Autodesk Fusion 360 part; units mm, degrees
(part 3 of 4)
sketch "ProMicro" plane through (0, 0, 0) normal (0, 0, -1) x (1, 0, 0) in component "Plate_Left"
  line L0 (111.75, 39.3) -> (111.75, 25.3)
  line L1 (101.75, 25.3) -> (97.75, 25.3)
  line L2 (97.75, 25.3) -> (97.75, 39.3)
  line L3 (97.75, 39.3) -> (101.75, 39.3)
  line L4 (92.7, 55.69) -> (92.7, 41.69)
  line L5 (92.7, 41.69) -> (88.7, 41.69)
  line L6 (78.7, 41.69) -> (78.7, 55.69)
  line L7 (88.7, 55.69) -> (92.7, 55.69)
  line L8 (59.65, 78.7) -> (59.65, 92.7)
  line L9 (59.65, 92.7) -> (63.65, 92.7)
  line L10 (73.65, 92.7) -> (73.65, 78.7)
  line L11 (63.65, 78.7) -> (59.65, 78.7)
  line L12 (59.65, 16.5) -> (63.65, 16.5)
  line L13 (73.65, 16.5) -> (73.65, 2.5)
  line L14 (63.65, 2.5) -> (59.65, 2.5)
  line L15 (59.65, 2.5) -> (59.65, 16.5)
  line L16 (40.6, 79.79) -> (40.6, 93.79)
  line L17 (40.6, 93.79) -> (44.6, 93.79)
  line L18 (54.6, 93.79) -> (54.6, 79.79)
  line L19 (44.6, 79.79) -> (40.6, 79.79)
  line L20 (31.55, 21.21) -> (35.55, 21.21)
  line L21 (35.55, 21.21) -> (35.55, 7.21)
  line L22 (35.55, 7.21) -> (31.55, 7.21)
  line L23 (21.55, 7.21) -> (21.55, 21.21)
  line L24 (12.5, 79.5) -> (16.5, 79.5)
  line L25 (16.5, 79.5) -> (16.5, 65.5)
  line L26 (16.5, 65.5) -> (12.5, 65.5)
  line L27 (2.5, 65.5) -> (2.5, 79.5)
  line L28 (2.5, 98.55) -> (6.5, 98.55)
  line L29 (16.5, 98.55) -> (16.5, 84.55)
  line L30 (6.5, 84.55) -> (2.5, 84.55)
  line L31 (2.5, 84.55) -> (2.5, 98.55)
  line L32 (2.5, 60.45) -> (6.5, 60.45)
  line L33 (16.5, 60.45) -> (16.5, 46.45)
  line L34 (6.5, 46.45) -> (2.5, 46.45)
  line L35 (2.5, 46.45) -> (2.5, 60.45)
  line L36 (35.55, 40.26) -> (35.55, 26.26)
  line L37 (25.55, 26.26) -> (21.55, 26.26)
  line L38 (21.55, 26.26) -> (21.55, 40.26)
  line L39 (21.55, 40.26) -> (25.55, 40.26)
  line L40 (54.6, 55.69) -> (54.6, 41.69)
  line L41 (54.6, 41.69) -> (50.6, 41.69)
  line L42 (40.6, 41.69) -> (40.6, 55.69)
  line L43 (50.6, 55.69) -> (54.6, 55.69)
  line L44 (73.65, 35.55) -> (73.65, 21.55)
  line L45 (63.65, 21.55) -> (59.65, 21.55)
  line L46 (59.65, 21.55) -> (59.65, 35.55)
  line L47 (59.65, 35.55) -> (63.65, 35.55)
  line L48 (90.1617, 83.0445) -> (84.4545, 95.8284)
  line L49 (93.5858, 99.9049) -> (97.2384, 101.5355)
  line L50 (97.2384, 101.5355) -> (102.9456, 88.7516)
  line L51 (102.9456, 88.7516) -> (99.293, 87.121)
  line L52 (92.7, 36.64) -> (92.7, 22.64)
  line L53 (82.7, 22.64) -> (78.7, 22.64)
  line L54 (78.7, 22.64) -> (78.7, 36.64)
  line L55 (78.7, 36.64) -> (82.7, 36.64)
  line L56 (111.75, 58.35) -> (111.75, 44.35)
  line L57 (111.75, 44.35) -> (107.75, 44.35)
  line L58 (97.75, 44.35) -> (97.75, 58.35)
  line L59 (107.75, 58.35) -> (111.75, 58.35)
  line L60 (107.75, 20.25) -> (111.75, 20.25)
  line L61 (111.75, 20.25) -> (111.75, 6.25)
  line L62 (111.75, 6.25) -> (107.75, 6.25)
  line L63 (97.75, 6.25) -> (97.75, 20.25)
  line L64 (78.7, 60.74) -> (78.7, 74.74)
  line L65 (88.7, 74.74) -> (92.7, 74.74)
  line L66 (92.7, 74.74) -> (92.7, 60.74)
  line L67 (92.7, 60.74) -> (88.7, 60.74)
  line L68 (59.65, 59.65) -> (59.65, 73.65)
  line L69 (69.65, 73.65) -> (73.65, 73.65)
  line L70 (73.65, 73.65) -> (73.65, 59.65)
  line L71 (73.65, 59.65) -> (69.65, 59.65)
  line L72 (40.6, 17.59) -> (44.6, 17.59)
  line L73 (54.6, 17.59) -> (54.6, 3.59)
  line L74 (44.6, 3.59) -> (40.6, 3.59)
  line L75 (40.6, 3.59) -> (40.6, 17.59)
  line L76 (40.6, 60.74) -> (40.6, 74.74)
  line L77 (50.6, 74.74) -> (54.6, 74.74)
  line L78 (54.6, 74.74) -> (54.6, 60.74)
  line L79 (54.6, 60.74) -> (50.6, 60.74)
  line L80 (16.5, 22.35) -> (16.5, 8.35)
  line L81 (16.5, 8.35) -> (12.5, 8.35)
  line L82 (2.5, 8.35) -> (2.5, 22.35)
  line L83 (12.5, 22.35) -> (16.5, 22.35)
  line L84 (21.55, 64.36) -> (21.55, 78.36)
  line L85 (31.55, 78.36) -> (35.55, 78.36)
  line L86 (35.55, 78.36) -> (35.55, 64.36)
  line L87 (35.55, 64.36) -> (31.55, 64.36)
  line L88 (21.55, 83.41) -> (21.55, 97.41)
  line L89 (21.55, 97.41) -> (25.55, 97.41)
  line L90 (35.55, 97.41) -> (35.55, 83.41)
  line L91 (25.55, 83.41) -> (21.55, 83.41)
  line L92 (2.5, 27.4) -> (2.5, 41.4)
  line L93 (12.5, 41.4) -> (16.5, 41.4)
  line L94 (16.5, 41.4) -> (16.5, 27.4)
  line L95 (16.5, 27.4) -> (12.5, 27.4)
  line L96 (35.55, 59.31) -> (35.55, 45.31)
  line L97 (35.55, 45.31) -> (31.55, 45.31)
  line L98 (21.55, 45.31) -> (21.55, 59.31)
  line L99 (31.55, 59.31) -> (35.55, 59.31)
  line L100 (54.6, 36.64) -> (54.6, 22.64)
  line L101 (44.6, 22.64) -> (40.6, 22.64)
  line L102 (40.6, 22.64) -> (40.6, 36.64)
  line L103 (40.6, 36.64) -> (44.6, 36.64)
  line L104 (73.65, 54.6) -> (73.65, 40.6)
  line L105 (63.65, 40.6) -> (59.65, 40.6)
  line L106 (59.65, 40.6) -> (59.65, 54.6)
  line L107 (59.65, 54.6) -> (63.65, 54.6)
  line L108 (112.7117, 92.7045) -> (107.0045, 105.4884)
  line L109 (116.1358, 109.5649) -> (119.7884, 111.1955)
  line L110 (119.7884, 111.1955) -> (125.4956, 98.4116)
  line L111 (125.4956, 98.4116) -> (121.843, 96.781)
  line L112 (88.7, 17.59) -> (92.7, 17.59)
  line L113 (92.7, 17.59) -> (92.7, 3.59)
  line L114 (92.7, 3.59) -> (88.7, 3.59)
  line L115 (78.7, 3.59) -> (78.7, 17.59)
  line L116 (97.75, 63.4) -> (97.75, 77.4)
  line L117 (107.75, 77.4) -> (111.75, 77.4)
  line L118 (111.75, 77.4) -> (111.75, 63.4)
  line L119 (111.75, 63.4) -> (107.75, 63.4)
  line L120 (119.3123, 118.9999) -> (83.6581, 103.172)
  arc A0 (82.8467, 103) -> (83.6581, 103.172) centre (82.8467, 105) ccw
  line L121 (82.8467, 103) -> (0, 103)
  arc A1 (0, 103) -> (-6, 97) centre (0, 97) ccw
  line L122 (-6, 97) -> (-6, 6.0028)
  arc A2 (-6, 6.0028) -> (0, 0.0028) centre (0, 6.0028) ccw
  line L123 (0, 0.0028) -> (135.25, 0.0028)
  arc A3 (135.25, 0.0028) -> (141.25, 6.0028) centre (135.25, 6.0028) ccw
  line L124 (141.25, 6.0028) -> (141.25, 113.172)
  arc A4 (141.25, 113.172) -> (135.25, 119.172) centre (135.25, 113.172) ccw
  line L125 (135.25, 119.172) -> (120.1238, 119.172)
  arc A5 (120.1238, 119.172) -> (119.3123, 118.9999) centre (120.1238, 117.172) ccw
  line L126 (114.2279, 1.5198) -> (114.2279, 35.3198)
  line L127 (114.2279, 35.3198) -> (132.7279, 35.3198)
  line L128 (132.7279, 35.3198) -> (132.7279, 1.5198)
  line L129 (132.7279, 1.5198) -> (114.2279, 1.5198)
  line L130 (118.9079, 0.0181) -> (118.9079, 1.5198)
  line L131 (127.8479, 1.5198) -> (127.8479, 0.0181)
  line L132 (118.9079, 0.0181) -> (127.8479, 0.0181)
  line L133 (126.4779, 35.3198) -> (120.4779, 35.3198)
  line L134 (126.4779, 35.3198) -> (126.4779, 34.3198)
  line L135 (126.4779, 34.3198) -> (120.4779, 34.3198)
  line L136 (120.4779, 34.3198) -> (120.4779, 35.3198)
  line L137 (126.4779, 35.3198) -> (126.4779, 36.3198)
  line L138 (126.4779, 36.3198) -> (120.4779, 36.3198)
  line L139 (120.4779, 36.3198) -> (120.4779, 35.3198)
  line L140 (101.75, 58.35) -> (101.75, 59.85)
  line L141 (101.75, 59.85) -> (107.75, 59.85)
  line L142 (107.75, 59.85) -> (107.75, 58.35)
  line L143 (107.75, 44.35) -> (107.75, 42.85)
  line L144 (107.75, 42.85) -> (101.75, 42.85)
  line L145 (101.75, 42.85) -> (101.75, 44.35)
  line L146 (101.75, 44.35) -> (97.75, 44.35)
  line L147 (97.75, 58.35) -> (101.75, 58.35)
  line L148 (88.7, 19.09) -> (88.7, 17.59)
  line L149 (88.7, 3.59) -> (88.7, 2.09)
  line L150 (88.7, 2.09) -> (82.7, 2.09)
  line L151 (82.7, 2.09) -> (82.7, 3.59)
  line L152 (82.7, 3.59) -> (78.7, 3.59)
  line L153 (78.7, 17.59) -> (82.7, 17.59)
  line L154 (82.7, 17.59) -> (82.7, 19.09)
  line L155 (82.7, 19.09) -> (88.7, 19.09)
  line L156 (88.7, 57.19) -> (88.7, 55.69)
  line L157 (88.7, 41.69) -> (88.7, 40.19)
  line L158 (88.7, 40.19) -> (82.7, 40.19)
  line L159 (82.7, 40.19) -> (82.7, 41.69)
  line L160 (82.7, 41.69) -> (78.7, 41.69)
  line L161 (78.7, 55.69) -> (82.7, 55.69)
  line L162 (82.7, 55.69) -> (82.7, 57.19)
  line L163 (82.7, 57.19) -> (88.7, 57.19)
  line L164 (101.75, 23.8) -> (101.75, 25.3)
  line L165 (101.75, 39.3) -> (101.75, 40.8)
  line L166 (101.75, 40.8) -> (107.75, 40.8)
  line L167 (107.75, 40.8) -> (107.75, 39.3)
  line L168 (107.75, 39.3) -> (111.75, 39.3)
  line L169 (111.75, 25.3) -> (107.75, 25.3)
  line L170 (107.75, 25.3) -> (107.75, 23.8)
  line L171 (107.75, 23.8) -> (101.75, 23.8)
  line L172 (107.75, 21.75) -> (107.75, 20.25)
  line L173 (107.75, 6.25) -> (107.75, 4.75)
  line L174 (107.75, 4.75) -> (101.75, 4.75)
  line L175 (101.75, 4.75) -> (101.75, 6.25)
  line L176 (101.75, 6.25) -> (97.75, 6.25)
  line L177 (97.75, 20.25) -> (101.75, 20.25)
  line L178 (101.75, 20.25) -> (101.75, 21.75)
  line L179 (101.75, 21.75) -> (107.75, 21.75)
  line L180 (82.7, 21.14) -> (82.7, 22.64)
  line L181 (82.7, 36.64) -> (82.7, 38.14)
  line L182 (82.7, 38.14) -> (88.7, 38.14)
  line L183 (88.7, 38.14) -> (88.7, 36.64)
  line L184 (88.7, 36.64) -> (92.7, 36.64)
  line L185 (92.7, 22.64) -> (88.7, 22.64)
  line L186 (88.7, 22.64) -> (88.7, 21.14)
  line L187 (88.7, 21.14) -> (82.7, 21.14)
  line L188 (88.7, 76.24) -> (88.7, 74.74)
  line L189 (88.7, 60.74) -> (88.7, 59.24)
  line L190 (88.7, 59.24) -> (82.7, 59.24)
  line L191 (82.7, 59.24) -> (82.7, 60.74)
  line L192 (82.7, 60.74) -> (78.7, 60.74)
  line L193 (78.7, 74.74) -> (82.7, 74.74)
  line L194 (82.7, 74.74) -> (82.7, 76.24)
  line L195 (82.7, 76.24) -> (88.7, 76.24)
  line L196 (63.65, 77.2) -> (63.65, 78.7)
  line L197 (63.65, 92.7) -> (63.65, 94.2)
  line L198 (63.65, 94.2) -> (69.65, 94.2)
  line L199 (69.65, 94.2) -> (69.65, 92.7)
  line L200 (69.65, 92.7) -> (73.65, 92.7)
  line L201 (73.65, 78.7) -> (69.65, 78.7)
  line L202 (69.65, 78.7) -> (69.65, 77.2)
  line L203 (69.65, 77.2) -> (63.65, 77.2)
  line L204 (50.6, 76.24) -> (50.6, 74.74)
  line L205 (50.6, 60.74) -> (50.6, 59.24)
  line L206 (50.6, 59.24) -> (44.6, 59.24)
  line L207 (44.6, 59.24) -> (44.6, 60.74)
  line L208 (44.6, 60.74) -> (40.6, 60.74)
  line L209 (40.6, 74.74) -> (44.6, 74.74)
  line L210 (44.6, 74.74) -> (44.6, 76.24)
  line L211 (44.6, 76.24) -> (50.6, 76.24)
  line L212 (25.55, 81.91) -> (25.55, 83.41)
  line L213 (25.55, 97.41) -> (25.55, 98.91)
  line L214 (25.55, 98.91) -> (31.55, 98.91)
  line L215 (31.55, 98.91) -> (31.55, 97.41)
  line L216 (31.55, 97.41) -> (35.55, 97.41)
  line L217 (35.55, 83.41) -> (31.55, 83.41)
  line L218 (31.55, 83.41) -> (31.55, 81.91)
  line L219 (31.55, 81.91) -> (25.55, 81.91)
  line L220 (63.65, 39.1) -> (63.65, 40.6)
  line L221 (63.65, 54.6) -> (63.65, 56.1)
  line L222 (63.65, 56.1) -> (69.65, 56.1)
  line L223 (69.65, 56.1) -> (69.65, 54.6)
  line L224 (69.65, 54.6) -> (73.65, 54.6)
  line L225 (73.65, 40.6) -> (69.65, 40.6)
  line L226 (69.65, 40.6) -> (69.65, 39.1)
  line L227 (69.65, 39.1) -> (63.65, 39.1)
  line L228 (25.55, 24.76) -> (25.55, 26.26)
  line L229 (25.55, 40.26) -> (25.55, 41.76)
  line L230 (25.55, 41.76) -> (31.55, 41.76)
  line L231 (31.55, 41.76) -> (31.55, 40.26)
  line L232 (31.55, 40.26) -> (35.55, 40.26)
  line L233 (35.55, 26.26) -> (31.55, 26.26)
  line L234 (31.55, 26.26) -> (31.55, 24.76)
  line L235 (31.55, 24.76) -> (25.55, 24.76)
  line L236 (12.5, 42.9) -> (12.5, 41.4)
  line L237 (12.5, 27.4) -> (12.5, 25.9)
  line L238 (12.5, 25.9) -> (6.5, 25.9)
  line L239 (6.5, 25.9) -> (6.5, 27.4)
  line L240 (6.5, 27.4) -> (2.5, 27.4)
  line L241 (2.5, 41.4) -> (6.5, 41.4)
  line L242 (6.5, 41.4) -> (6.5, 42.9)
  line L243 (6.5, 42.9) -> (12.5, 42.9)
  line L244 (12.5, 23.85) -> (12.5, 22.35)
  line L245 (12.5, 8.35) -> (12.5, 6.85)
  line L246 (12.5, 6.85) -> (6.5, 6.85)
  line L247 (6.5, 6.85) -> (6.5, 8.35)
  line L248 (6.5, 8.35) -> (2.5, 8.35)
  line L249 (2.5, 22.35) -> (6.5, 22.35)
  line L250 (6.5, 22.35) -> (6.5, 23.85)
  line L251 (6.5, 23.85) -> (12.5, 23.85)
  line L252 (44.6, 21.14) -> (44.6, 22.64)
  line L253 (44.6, 36.64) -> (44.6, 38.14)
  line L254 (44.6, 38.14) -> (50.6, 38.14)
  line L255 (50.6, 38.14) -> (50.6, 36.64)
  line L256 (50.6, 36.64) -> (54.6, 36.64)
  line L257 (54.6, 22.64) -> (50.6, 22.64)
  line L258 (50.6, 22.64) -> (50.6, 21.14)
  line L259 (50.6, 21.14) -> (44.6, 21.14)
  line L260 (63.65, 20.05) -> (63.65, 21.55)
  line L261 (63.65, 35.55) -> (63.65, 37.05)
  line L262 (63.65, 37.05) -> (69.65, 37.05)
  line L263 (69.65, 37.05) -> (69.65, 35.55)
  line L264 (69.65, 35.55) -> (73.65, 35.55)
  line L265 (73.65, 21.55) -> (69.65, 21.55)
  line L266 (69.65, 21.55) -> (69.65, 20.05)
  line L267 (69.65, 20.05) -> (63.65, 20.05)
  line L268 (31.55, 60.81) -> (31.55, 59.31)
  line L269 (31.55, 45.31) -> (31.55, 43.81)
  line L270 (31.55, 43.81) -> (25.55, 43.81)
  line L271 (25.55, 43.81) -> (25.55, 45.31)
  line L272 (25.55, 45.31) -> (21.55, 45.31)
  line L273 (21.55, 59.31) -> (25.55, 59.31)
  line L274 (25.55, 59.31) -> (25.55, 60.81)
  line L275 (25.55, 60.81) -> (31.55, 60.81)
  line L276 (6.5, 83.05) -> (6.5, 84.55)
  line L277 (6.5, 98.55) -> (6.5, 100.05)
  line L278 (6.5, 100.05) -> (12.5, 100.05)
  line L279 (12.5, 100.05) -> (12.5, 98.55)
  line L280 (12.5, 98.55) -> (16.5, 98.55)
  line L281 (16.5, 84.55) -> (12.5, 84.55)
  line L282 (12.5, 84.55) -> (12.5, 83.05)
  line L283 (12.5, 83.05) -> (6.5, 83.05)
  line L284 (31.55, 79.86) -> (31.55, 78.36)
  line L285 (31.55, 64.36) -> (31.55, 62.86)
  line L286 (31.55, 62.86) -> (25.55, 62.86)
  line L287 (25.55, 62.86) -> (25.55, 64.36)
  line L288 (25.55, 64.36) -> (21.55, 64.36)
  line L289 (21.55, 78.36) -> (25.55, 78.36)
  line L290 (25.55, 78.36) -> (25.55, 79.86)
  line L291 (25.55, 79.86) -> (31.55, 79.86)
  line L292 (107.75, 78.9) -> (107.75, 77.4)
  line L293 (107.75, 63.4) -> (107.75, 61.9)
  line L294 (107.75, 61.9) -> (101.75, 61.9)
  line L295 (101.75, 61.9) -> (101.75, 63.4)
  line L296 (101.75, 63.4) -> (97.75, 63.4)
  line L297 (97.75, 77.4) -> (101.75, 77.4)
  line L298 (101.75, 77.4) -> (101.75, 78.9)
  line L299 (101.75, 78.9) -> (107.75, 78.9)
  line L300 (6.5, 79.5) -> (6.5, 81)
  line L301 (6.5, 81) -> (12.5, 81)
  line L302 (12.5, 81) -> (12.5, 79.5)
  line L303 (12.5, 65.5) -> (12.5, 64)
  line L304 (12.5, 64) -> (6.5, 64)
  line L305 (6.5, 64) -> (6.5, 65.5)
  line L306 (6.5, 65.5) -> (2.5, 65.5)
  line L307 (2.5, 79.5) -> (6.5, 79.5)
  line L308 (44.6, 55.69) -> (44.6, 57.19)
  line L309 (44.6, 57.19) -> (50.6, 57.19)
  line L310 (50.6, 57.19) -> (50.6, 55.69)
  line L311 (50.6, 41.69) -> (50.6, 40.19)
  line L312 (50.6, 40.19) -> (44.6, 40.19)
  line L313 (44.6, 40.19) -> (44.6, 41.69)
  line L314 (44.6, 41.69) -> (40.6, 41.69)
  line L315 (40.6, 55.69) -> (44.6, 55.69)
  line L316 (25.55, 21.21) -> (25.55, 22.71)
  line L317 (25.55, 22.71) -> (31.55, 22.71)
  line L318 (31.55, 22.71) -> (31.55, 21.21)
  line L319 (31.55, 7.21) -> (31.55, 5.71)
  line L320 (31.55, 5.71) -> (25.55, 5.71)
  line L321 (25.55, 5.71) -> (25.55, 7.21)
  line L322 (25.55, 7.21) -> (21.55, 7.21)
  line L323 (21.55, 21.21) -> (25.55, 21.21)
  line L324 (63.65, 1) -> (63.65, 2.5)
  line L325 (63.65, 16.5) -> (63.65, 18)
  line L326 (63.65, 18) -> (69.65, 18)
  line L327 (69.65, 18) -> (69.65, 16.5)
  line L328 (69.65, 16.5) -> (73.65, 16.5)
  line L329 (73.65, 2.5) -> (69.65, 2.5)
  line L330 (69.65, 2.5) -> (69.65, 1)
  line L331 (69.65, 1) -> (63.65, 1)
  line L332 (63.65, 73.65) -> (63.65, 75.15)
  line L333 (63.65, 75.15) -> (69.65, 75.15)
  line L334 (69.65, 75.15) -> (69.65, 73.65)
  line L335 (69.65, 59.65) -> (69.65, 58.15)
  line L336 (69.65, 58.15) -> (63.65, 58.15)
  line L337 (63.65, 58.15) -> (63.65, 59.65)
  line L338 (63.65, 59.65) -> (59.65, 59.65)
  line L339 (59.65, 73.65) -> (63.65, 73.65)
  line L340 (50.6, 79.79) -> (50.6, 78.29)
  line L341 (50.6, 78.29) -> (44.6, 78.29)
  line L342 (44.6, 78.29) -> (44.6, 79.79)
  line L343 (44.6, 93.79) -> (44.6, 95.29)
  line L344 (44.6, 95.29) -> (50.6, 95.29)
  line L345 (50.6, 95.29) -> (50.6, 93.79)
  line L346 (50.6, 93.79) -> (54.6, 93.79)
  line L347 (54.6, 79.79) -> (50.6, 79.79)
  line L348 (12.5, 46.45) -> (12.5, 44.95)
  line L349 (12.5, 44.95) -> (6.5, 44.95)
  line L350 (6.5, 44.95) -> (6.5, 46.45)
  line L351 (6.5, 60.45) -> (6.5, 61.95)
  line L352 (6.5, 61.95) -> (12.5, 61.95)
  line L353 (12.5, 61.95) -> (12.5, 60.45)
  line L354 (12.5, 60.45) -> (16.5, 60.45)
  line L355 (16.5, 46.45) -> (12.5, 46.45)
  line L356 (50.6, 3.59) -> (50.6, 2.09)
  line L357 (50.6, 2.09) -> (44.6, 2.09)
  line L358 (44.6, 2.09) -> (44.6, 3.59)
  line L359 (44.6, 17.59) -> (44.6, 19.09)
  line L360 (44.6, 19.09) -> (50.6, 19.09)
  line L361 (50.6, 19.09) -> (50.6, 17.59)
  line L362 (50.6, 17.59) -> (54.6, 17.59)
  line L363 (54.6, 3.59) -> (50.6, 3.59)
  line L364 (92.9744, 101.2746) -> (93.5858, 99.9049)
  line L365 (99.293, 87.121) -> (99.9045, 85.7513)
  line L366 (99.9045, 85.7513) -> (94.4257, 83.3054)
  line L367 (94.4257, 83.3054) -> (93.8142, 84.6751)
  line L368 (93.8142, 84.6751) -> (90.1617, 83.0445)
  line L369 (84.4545, 95.8284) -> (88.107, 97.459)
  line L370 (88.107, 97.459) -> (87.4955, 98.8287)
  line L371 (87.4955, 98.8287) -> (92.9744, 101.2746)
  line L372 (115.5244, 110.9346) -> (116.1358, 109.5649)
  line L373 (121.843, 96.781) -> (122.4545, 95.4113)
  line L374 (122.4545, 95.4113) -> (116.9757, 92.9654)
  line L375 (116.9757, 92.9654) -> (116.3642, 94.3351)
  line L376 (116.3642, 94.3351) -> (112.7117, 92.7045)
  line L377 (107.0045, 105.4884) -> (110.657, 107.119)
  line L378 (110.657, 107.119) -> (110.0455, 108.4887)
  line L379 (110.0455, 108.4887) -> (115.5244, 110.9346)
  line L380 (117.2279, 35.3198) -> (117.2279, 15.3198)
  line L381 (117.2279, 15.3198) -> (129.7279, 15.3198)
  line L382 (129.7279, 15.3198) -> (129.7279, 35.3198)
  line L383 (129.7279, 15.3198) -> (132.7279, 15.3198) construction
  line L384 (117.2279, 15.3198) -> (114.2279, 15.3198) construction
  line L385 (141.25, 45.3198) -> (126.75, 45.3198)
  line L386 (126.75, 45.3198) -> (126.75, 54.3198)
  line L387 (126.75, 54.3198) -> (141.25, 54.3198)
  line L388 (141.25, 54.3198) -> (141.25, 45.3198)
  point P0 (123.4779, 1.5198)
  point P1 (123.4779, 35.3198)
  dimension "d218" = 33.8
  dimension "d219" = 18.5
  dimension "d220" = 8.94
  dimension "d221" = 1.5017
  dimension "d222" = 4.68
  dimension "d227" = 6
  dimension "d228" = 1
  dimension "d229" = 1
  dimension "d453" = 20
  dimension "d454" = 3
  dimension "d495" = 14.5
  dimension "d496" = 9
  dimension "d497" = 10
  constraint coincident L129 L131.start
  constraint perpendicular L129 L131
  constraint coincident L129 L130.end
  constraint perpendicular L129 L130
  constraint perpendicular L131 L132
  constraint perpendicular L126 L129
  constraint perpendicular L128 L129
  constraint perpendicular L127 L128
  constraint vertical L126
  constraint midpoint L129 P0
  constraint midpoint L127 P1
  constraint parallel L127 L133
  constraint midpoint P1 L133
  constraint perpendicular L133 L134
  constraint perpendicular L134 L135
  constraint perpendicular L127 L136
  constraint perpendicular L127 L137
  constraint perpendicular L136 L138
  constraint perpendicular L133 L139
  constraint coincident L127 L380.start
  constraint perpendicular L127 L380
  constraint perpendicular L380 L381
  constraint coincident L127 L382.end
  constraint perpendicular L127 L382
  constraint coincident L128 L383.end
  constraint perpendicular L128 L383
  constraint coincident L126 L384.end
  constraint perpendicular L126 L384
  constraint equal L383 L384
  constraint horizontal L385
  constraint vertical L386
  constraint horizontal L387
  constraint vertical L388
  constraint coincident L124 L385.start
  measures "d218" distance of L127.end L128.end
  measures "d219" distance of L126.start L128.end
  measures "d220" distance of L130.start L131.end
  measures "d221" distance of L130.start L130.end
  measures "d222" distance of L126.start L130.end
  measures "d227" distance of L133.start L133.end
  measures "d228" distance of L133.start L134.end
  measures "d229" distance of L133.start L137.end
  measures "d453" distance of L380.start L380.end
  measures "d454" distance of L380.end L384.end
  measures "d495" distance of L385.start L385.end
  measures "d496" distance of L385.start L387.end
  measures "d497" distance of L127 L385
extrude "Extrude6" cut sketch "ProMicro" against normal blind 1.6 contours L126 L127 L128 L129 L380 L381 L382 | L127 L134 L135 L136 L380 L381 L382 | L127 L133 L134 L135 L136 bodies 1 in component "Plate_Left"
extrude "Extrude14" cut sketch "ProMicro" against normal blind 0.8 from surface at -1.6 contours L126 L127 L128 L129 L380 L381 L382 bodies 1 in component "Plate_Left"
extrude "Extrude8" add sketch "ProMicro" along normal blind 1 contours L127 L133 L137 L138 L139 | L127 L133 L134 L135 L136 bodies 1 in component "Plate_Left"
fillet "Fillet3" radius 1 1 edges at (123.4779, -34.3198, 0) on bodies 1 in component "Plate_Left"
chamfer "Chamfer1" distance 0.5 angle 45 3 edges at (126.4779, -35.8198, 0) (123.4779, -36.3198, 0) (120.4779, -35.8198, 0) on bodies 1 in component "Plate_Left"
fillet "Fillet4" radius 0.4 1 edges at (123.4779, -34.3198, -1) on bodies 1 in component "Plate_Left"
sketch "USB_C_MCU" plane through (0, -0.0028, 0) normal (0, 1, 0) x (-1, 0, 0) in component "Plate_Left"
  line L0 (-135.25, 5) -> (-135.25, 0)
  line L1 (-135.25, 0) -> (0, 0)
  line L2 (0, 0) -> (0, 5)
  line L3 (-132.7279, 0) -> (-132.7279, 2.4)
  line L4 (-118.9779, -1.45) -> (-118.9779, -0.7)
  line L5 (-120.1779, 0.5) -> (-126.7779, 0.5)
  line L6 (-127.9779, -0.7) -> (-127.9779, -1.45)
  arc A0 (-120.1779, -2.65) -> (-118.9779, -1.45) centre (-120.1779, -1.45) ccw
  arc A1 (-118.9779, -0.7) -> (-120.1779, 0.5) centre (-120.1779, -0.7) ccw
  arc A2 (-127.9779, -1.45) -> (-126.7779, -2.65) centre (-126.7779, -1.45) ccw
  line L7 (-126.7779, -2.65) -> (-120.1779, -2.65)
  arc A3 (-126.7779, 0.5) -> (-127.9779, -0.7) centre (-126.7779, -0.7) ccw
  line L8 (-129.7279, 1.6) -> (-117.2279, 1.6)
  line L9 (-123.4779, 0.5) -> (-123.4779, 1.6) construction
  line L10 (0, 5) -> (-135.25, 5)
  line L11 (-117.2279, 1.6) -> (-129.7279, 1.6)
  dimension "d443" = 1.1
  dimension "d444" = 0.75
  dimension "d445" = 1.2
  dimension "d446" = 6.6
  dimension "d447" = 9
  dimension "d448" = 3.15
  constraint vertical L9
  constraint midpoint L5 L9.start
  constraint equal L5 L7
  constraint horizontal L7
  constraint horizontal L5
  constraint vertical L4
  constraint vertical L6
  constraint equal L4 L6
  constraint equal A1 A2
  constraint equal A0 A3
  constraint equal A0 A2
  measures "d443" distance of L9.start L9.end
  measures "d444" distance of L4.end L4.start
  measures "d445" radius of A2
  measures "d446" distance of A2.end A0.start
  measures "d447" distance of L4 L6
  measures "d448" distance of L5 L7
sketch "Sketch10" plane through (141.25, 0, 0) normal (1, 0, 0) x (0, 1, 0) in component "Plate_Left"
  line L0 (-113.172, 0) -> (-6.0028, 0)
  line L1 (-6.0028, 0) -> (-6.0028, 5)
  line L2 (-6.0028, 5) -> (-113.172, 5)
  line L3 (-113.172, 5) -> (-113.172, 0)
  line L4 (-45.3198, -0.375) -> (-45.3198, 0.375)
  arc A0 (-45.3198, 0.375) -> (-46.5198, 1.575) centre (-46.5198, 0.375) ccw
  line L5 (-46.5198, 1.575) -> (-53.1198, 1.575)
  arc A1 (-53.1198, 1.575) -> (-54.3198, 0.375) centre (-53.1198, 0.375) ccw
  line L6 (-54.3198, 0.375) -> (-54.3198, -0.375)
  arc A2 (-54.3198, -0.375) -> (-53.1198, -1.575) centre (-53.1198, -0.375) ccw
  line L7 (-53.1198, -1.575) -> (-46.5198, -1.575)
  arc A3 (-46.5198, -1.575) -> (-45.3198, -0.375) centre (-46.5198, -0.375) ccw
  line L8 (-54.3198, 0) -> (-45.3198, 0)
  line L9 (-54.3198, 0) -> (-45.3198, 0)
  dimension "d490" = 0.75
  dimension "d491" = 1.2
  dimension "d492" = 6.6
  dimension "d493" = 9
  dimension "d494" = 3.15
  constraint equal L5 L7
  constraint horizontal L7
  constraint horizontal L5
  constraint vertical L4
  constraint vertical L6
  constraint equal L4 L6
  constraint equal A0 A2
  constraint equal A1 A3
  constraint equal A2 A3
  constraint midpoint L6 L8.start
  constraint midpoint L4 L8.end
  constraint midpoint L8 L9
  measures "d490" distance of L4.end L4.start
  measures "d491" radius of A2
  measures "d492" distance of A2.end L7.end
  measures "d493" distance of L4 L6
  measures "d494" distance of L5 L7
extrude "Extrude15" cut sketch "Sketch10" against normal blind 10.6 contours L0 L4 A0 L5 A1 L6 L8 L9 bodies 1 in component "Plate_Left"
extrude "Extrude16" cut sketch "ProMicro" against normal blind 0.4 contours L124 L385 L386 L387 L388 bodies 1 in component "Plate_Left"
move_face "OffsetFaces3" offset -0.1 5 faces at (136.4167, -45.3198, 0.1333) (137.7167, -46.0795, 1.4913) (137.7167, -48.7198, 1.575) (134.1834, -53.5073, 1.5107) (136.4167, -54.3198, 0.2667) on bodies 1 in component "Plate_Left"
extrude "Extrude9" cut sketch "USB_C_MCU" against normal up to surface (1.517 mm away) contours L1 L5 A1 A3 bodies 1 in component "Plate_Left"
move_face "OffsetFaces1" offset -0.1 3 faces at (122.3779, -0.5085, 0.5) (119.9093, -1.0141, 0.4696) (127.0464, -1.0141, 0.4696) on bodies 1 in component "Plate_Left"
sketch "Screw_Holes" plane through (0, 0, 5) normal (0, 0, 1) x (-1, 0, 0) in component "Plate_Left"
  line L0 (-111.75, 25.3) -> (-111.75, 39.3)
  line L1 (-111.75, 39.3) -> (-97.75, 39.3)
  line L2 (-97.75, 39.3) -> (-97.75, 25.3)
  line L3 (-97.75, 25.3) -> (-111.75, 25.3)
  line L4 (-92.7, 41.69) -> (-92.7, 55.69)
  line L5 (-92.7, 55.69) -> (-78.7, 55.69)
  line L6 (-78.7, 55.69) -> (-78.7, 41.69)
  line L7 (-78.7, 41.69) -> (-92.7, 41.69)
  line L8 (-59.65, 92.7) -> (-59.65, 78.7)
  line L9 (-59.65, 78.7) -> (-73.65, 78.7)
  line L10 (-73.65, 78.7) -> (-73.65, 92.7)
  line L11 (-73.65, 92.7) -> (-59.65, 92.7)
  line L12 (-73.65, 16.5) -> (-59.65, 16.5)
  line L13 (-59.65, 16.5) -> (-59.65, 2.5)
  line L14 (-59.65, 2.5) -> (-73.65, 2.5)
  line L15 (-73.65, 2.5) -> (-73.65, 16.5)
  line L16 (-40.6, 93.79) -> (-40.6, 79.79)
  line L17 (-40.6, 79.79) -> (-54.6, 79.79)
  line L18 (-54.6, 79.79) -> (-54.6, 93.79)
  line L19 (-54.6, 93.79) -> (-40.6, 93.79)
  line L20 (-35.55, 21.21) -> (-21.55, 21.21)
  line L21 (-21.55, 21.21) -> (-21.55, 7.21)
  line L22 (-21.55, 7.21) -> (-35.55, 7.21)
  line L23 (-35.55, 7.21) -> (-35.55, 21.21)
  line L24 (-16.5, 79.5) -> (-2.5, 79.5)
  line L25 (-2.5, 79.5) -> (-2.5, 65.5)
  line L26 (-2.5, 65.5) -> (-16.5, 65.5)
  line L27 (-16.5, 65.5) -> (-16.5, 79.5)
  line L28 (-16.5, 98.55) -> (-2.5, 98.55)
  line L29 (-2.5, 98.55) -> (-2.5, 84.55)
  line L30 (-2.5, 84.55) -> (-16.5, 84.55)
  line L31 (-16.5, 84.55) -> (-16.5, 98.55)
  line L32 (-16.5, 60.45) -> (-2.5, 60.45)
  line L33 (-2.5, 60.45) -> (-2.5, 46.45)
  line L34 (-2.5, 46.45) -> (-16.5, 46.45)
  line L35 (-16.5, 46.45) -> (-16.5, 60.45)
  line L36 (-35.55, 26.26) -> (-35.55, 40.26)
  line L37 (-35.55, 40.26) -> (-21.55, 40.26)
  line L38 (-21.55, 40.26) -> (-21.55, 26.26)
  line L39 (-21.55, 26.26) -> (-35.55, 26.26)
  line L40 (-54.6, 41.69) -> (-54.6, 55.69)
  line L41 (-54.6, 55.69) -> (-40.6, 55.69)
  line L42 (-40.6, 55.69) -> (-40.6, 41.69)
  line L43 (-40.6, 41.69) -> (-54.6, 41.69)
  line L44 (-73.65, 21.55) -> (-73.65, 35.55)
  line L45 (-73.65, 35.55) -> (-59.65, 35.55)
  line L46 (-59.65, 35.55) -> (-59.65, 21.55)
  line L47 (-59.65, 21.55) -> (-73.65, 21.55)
  line L48 (-84.4545, 95.8284) -> (-90.1617, 83.0445)
  line L49 (-90.1617, 83.0445) -> (-102.9456, 88.7516)
  line L50 (-102.9456, 88.7516) -> (-97.2384, 101.5355)
  line L51 (-97.2384, 101.5355) -> (-84.4545, 95.8284)
  line L52 (-92.7, 22.64) -> (-92.7, 36.64)
  line L53 (-92.7, 36.64) -> (-78.7, 36.64)
  line L54 (-78.7, 36.64) -> (-78.7, 22.64)
  line L55 (-78.7, 22.64) -> (-92.7, 22.64)
  line L56 (-111.75, 44.35) -> (-111.75, 58.35)
  line L57 (-111.75, 58.35) -> (-97.75, 58.35)
  line L58 (-97.75, 58.35) -> (-97.75, 44.35)
  line L59 (-97.75, 44.35) -> (-111.75, 44.35)
  line L60 (-111.75, 20.25) -> (-97.75, 20.25)
  line L61 (-97.75, 20.25) -> (-97.75, 6.25)
  line L62 (-97.75, 6.25) -> (-111.75, 6.25)
  line L63 (-111.75, 6.25) -> (-111.75, 20.25)
  line L64 (-78.7, 74.74) -> (-78.7, 60.74)
  line L65 (-78.7, 60.74) -> (-92.7, 60.74)
  line L66 (-92.7, 60.74) -> (-92.7, 74.74)
  line L67 (-92.7, 74.74) -> (-78.7, 74.74)
  line L68 (-59.65, 73.65) -> (-59.65, 59.65)
  line L69 (-59.65, 59.65) -> (-73.65, 59.65)
  line L70 (-73.65, 59.65) -> (-73.65, 73.65)
  line L71 (-73.65, 73.65) -> (-59.65, 73.65)
  line L72 (-54.6, 17.59) -> (-40.6, 17.59)
  line L73 (-40.6, 17.59) -> (-40.6, 3.59)
  line L74 (-40.6, 3.59) -> (-54.6, 3.59)
  line L75 (-54.6, 3.59) -> (-54.6, 17.59)
  line L76 (-40.6, 74.74) -> (-40.6, 60.74)
  line L77 (-40.6, 60.74) -> (-54.6, 60.74)
  line L78 (-54.6, 60.74) -> (-54.6, 74.74)
  line L79 (-54.6, 74.74) -> (-40.6, 74.74)
  line L80 (-16.5, 8.35) -> (-16.5, 22.35)
  line L81 (-16.5, 22.35) -> (-2.5, 22.35)
  line L82 (-2.5, 22.35) -> (-2.5, 8.35)
  line L83 (-2.5, 8.35) -> (-16.5, 8.35)
  line L84 (-21.55, 78.36) -> (-21.55, 64.36)
  line L85 (-21.55, 64.36) -> (-35.55, 64.36)
  line L86 (-35.55, 64.36) -> (-35.55, 78.36)
  line L87 (-35.55, 78.36) -> (-21.55, 78.36)
  line L88 (-21.55, 97.41) -> (-21.55, 83.41)
  line L89 (-21.55, 83.41) -> (-35.55, 83.41)
  line L90 (-35.55, 83.41) -> (-35.55, 97.41)
  line L91 (-35.55, 97.41) -> (-21.55, 97.41)
  line L92 (-2.5, 41.4) -> (-2.5, 27.4)
  line L93 (-2.5, 27.4) -> (-16.5, 27.4)
  line L94 (-16.5, 27.4) -> (-16.5, 41.4)
  line L95 (-16.5, 41.4) -> (-2.5, 41.4)
  line L96 (-35.55, 45.31) -> (-35.55, 59.31)
  line L97 (-35.55, 59.31) -> (-21.55, 59.31)
  line L98 (-21.55, 59.31) -> (-21.55, 45.31)
  line L99 (-21.55, 45.31) -> (-35.55, 45.31)
  line L100 (-54.6, 22.64) -> (-54.6, 36.64)
  line L101 (-54.6, 36.64) -> (-40.6, 36.64)
  line L102 (-40.6, 36.64) -> (-40.6, 22.64)
  line L103 (-40.6, 22.64) -> (-54.6, 22.64)
  line L104 (-73.65, 40.6) -> (-73.65, 54.6)
  line L105 (-73.65, 54.6) -> (-59.65, 54.6)
  line L106 (-59.65, 54.6) -> (-59.65, 40.6)
  line L107 (-59.65, 40.6) -> (-73.65, 40.6)
  line L108 (-107.0045, 105.4884) -> (-112.7117, 92.7045)
  line L109 (-112.7117, 92.7045) -> (-125.4956, 98.4116)
  line L110 (-125.4956, 98.4116) -> (-119.7884, 111.1955)
  line L111 (-119.7884, 111.1955) -> (-107.0045, 105.4884)
  line L112 (-92.7, 17.59) -> (-78.7, 17.59)
  line L113 (-78.7, 17.59) -> (-78.7, 3.59)
  line L114 (-78.7, 3.59) -> (-92.7, 3.59)
  line L115 (-92.7, 3.59) -> (-92.7, 17.59)
  line L116 (-97.75, 77.4) -> (-97.75, 63.4)
  line L117 (-97.75, 63.4) -> (-111.75, 63.4)
  line L118 (-111.75, 63.4) -> (-111.75, 77.4)
  line L119 (-111.75, 77.4) -> (-97.75, 77.4)
  line L120 (-83.6581, 103.172) -> (-119.3123, 118.9999)
  arc A0 (-119.3123, 118.9999) -> (-120.1238, 119.172) centre (-120.1238, 117.172) ccw
  line L121 (-120.1238, 119.172) -> (-135.25, 119.172)
  arc A1 (-135.25, 119.172) -> (-141.25, 113.172) centre (-135.25, 113.172) ccw
  line L122 (-141.25, 113.172) -> (-141.25, 6.0028)
  arc A2 (-141.25, 6.0028) -> (-135.25, 0.0028) centre (-135.25, 6.0028) ccw
  line L123 (-135.25, 0.0028) -> (0, 0.0028)
  arc A3 (0, 0.0028) -> (6, 6.0028) centre (0, 6.0028) ccw
  line L124 (6, 6.0028) -> (6, 97)
  arc A4 (6, 97) -> (0, 103) centre (0, 97) ccw
  line L125 (0, 103) -> (-82.8467, 103)
  arc A5 (-83.6581, 103.172) -> (-82.8467, 103) centre (-82.8467, 105) ccw
  line L126 (-119.0824, 0.0028) -> (-119.0824, 1.5198)
  line L127 (-119.0824, 1.5198) -> (-114.2279, 1.5198)
  line L128 (-114.2279, 1.5198) -> (-114.2279, 35.3198)
  line L129 (-114.2279, 35.3198) -> (-119.9779, 35.3198)
  line L130 (-119.9779, 35.3198) -> (-119.9779, 36.8198)
  line L131 (-119.9779, 36.8198) -> (-126.9779, 36.8198)
  line L132 (-126.9779, 36.8198) -> (-126.9779, 35.3198)
  line L133 (-126.9779, 35.3198) -> (-132.7279, 35.3198)
  line L134 (-132.7279, 35.3198) -> (-132.7279, 1.5198)
  line L135 (-132.7279, 1.5198) -> (-127.8733, 1.5198)
  line L136 (-127.8733, 1.5198) -> (-127.8733, 0.0028)
  line L137 (-127.8733, 0.0028) -> (-135.25, 0.0028)
  arc A6 (-141.25, 6.0028) -> (-135.25, 0.0028) centre (-135.25, 6.0028) ccw
  line L138 (-141.25, 6.0028) -> (-141.25, 45.2198)
  arc A7 (-135.25, 119.172) -> (-141.25, 113.172) centre (-135.25, 113.172) ccw
  line L139 (-135.25, 119.172) -> (-120.1238, 119.172)
  arc A8 (-119.3123, 118.9999) -> (-120.1238, 119.172) centre (-120.1238, 117.172) ccw
  line L140 (-119.3123, 118.9999) -> (-83.6581, 103.172)
  arc A9 (-83.6581, 103.172) -> (-82.8467, 103) centre (-82.8467, 105) ccw
  line L141 (-82.8467, 103) -> (0, 103)
  arc A10 (6, 97) -> (0, 103) centre (0, 97) ccw
  line L142 (6, 97) -> (6, 6.0028)
  arc A11 (0, 0.0028) -> (6, 6.0028) centre (0, 6.0028) ccw
  line L143 (0, 0.0028) -> (-119.0824, 0.0028)
  line L144 (-50.6, 3.59) -> (-50.6, 2.09)
  line L145 (-50.6, 2.09) -> (-44.6, 2.09)
  line L146 (-44.6, 2.09) -> (-44.6, 3.59)
  line L147 (-44.6, 3.59) -> (-40.6, 3.59)
  line L148 (-40.6, 3.59) -> (-40.6, 17.59)
  line L149 (-40.6, 17.59) -> (-44.6, 17.59)
  line L150 (-44.6, 17.59) -> (-44.6, 19.09)
  line L151 (-44.6, 19.09) -> (-50.6, 19.09)
  line L152 (-50.6, 19.09) -> (-50.6, 17.59)
  line L153 (-50.6, 17.59) -> (-54.6, 17.59)
  line L154 (-54.6, 17.59) -> (-54.6, 3.59)
  line L155 (-54.6, 3.59) -> (-50.6, 3.59)
  line L156 (-101.75, 58.35) -> (-101.75, 59.85)
  line L157 (-101.75, 59.85) -> (-107.75, 59.85)
  line L158 (-107.75, 59.85) -> (-107.75, 58.35)
  line L159 (-107.75, 58.35) -> (-111.75, 58.35)
  line L160 (-111.75, 58.35) -> (-111.75, 44.35)
  line L161 (-111.75, 44.35) -> (-107.75, 44.35)
  line L162 (-107.75, 44.35) -> (-107.75, 42.85)
  line L163 (-107.75, 42.85) -> (-101.75, 42.85)
  line L164 (-101.75, 42.85) -> (-101.75, 44.35)
  line L165 (-101.75, 44.35) -> (-97.75, 44.35)
  line L166 (-97.75, 44.35) -> (-97.75, 58.35)
  line L167 (-97.75, 58.35) -> (-101.75, 58.35)
  line L168 (-12.5, 46.45) -> (-12.5, 44.95)
  line L169 (-12.5, 44.95) -> (-6.5, 44.95)
  line L170 (-6.5, 44.95) -> (-6.5, 46.45)
  line L171 (-6.5, 46.45) -> (-2.5, 46.45)
  line L172 (-2.5, 46.45) -> (-2.5, 60.45)
  line L173 (-2.5, 60.45) -> (-6.5, 60.45)
  line L174 (-6.5, 60.45) -> (-6.5, 61.95)
  line L175 (-6.5, 61.95) -> (-12.5, 61.95)
  line L176 (-12.5, 61.95) -> (-12.5, 60.45)
  line L177 (-12.5, 60.45) -> (-16.5, 60.45)
  line L178 (-16.5, 60.45) -> (-16.5, 46.45)
  line L179 (-16.5, 46.45) -> (-12.5, 46.45)
  line L180 (-50.6, 79.79) -> (-50.6, 78.29)
  line L181 (-50.6, 78.29) -> (-44.6, 78.29)
  line L182 (-44.6, 78.29) -> (-44.6, 79.79)
  line L183 (-44.6, 79.79) -> (-40.6, 79.79)
  line L184 (-40.6, 79.79) -> (-40.6, 93.79)
  line L185 (-40.6, 93.79) -> (-44.6, 93.79)
  line L186 (-44.6, 93.79) -> (-44.6, 95.29)
  line L187 (-44.6, 95.29) -> (-50.6, 95.29)
  line L188 (-50.6, 95.29) -> (-50.6, 93.79)
  line L189 (-50.6, 93.79) -> (-54.6, 93.79)
  line L190 (-54.6, 93.79) -> (-54.6, 79.79)
  line L191 (-54.6, 79.79) -> (-50.6, 79.79)
  line L192 (-63.65, 73.65) -> (-63.65, 75.15)
  line L193 (-63.65, 75.15) -> (-69.65, 75.15)
  line L194 (-69.65, 75.15) -> (-69.65, 73.65)
  line L195 (-69.65, 73.65) -> (-73.65, 73.65)
  line L196 (-73.65, 73.65) -> (-73.65, 59.65)
  line L197 (-73.65, 59.65) -> (-69.65, 59.65)
  line L198 (-69.65, 59.65) -> (-69.65, 58.15)
  line L199 (-69.65, 58.15) -> (-63.65, 58.15)
  line L200 (-63.65, 58.15) -> (-63.65, 59.65)
  line L201 (-63.65, 59.65) -> (-59.65, 59.65)
  line L202 (-59.65, 59.65) -> (-59.65, 73.65)
  line L203 (-59.65, 73.65) -> (-63.65, 73.65)
  line L204 (-63.65, 1) -> (-63.65, 2.5)
  line L205 (-63.65, 2.5) -> (-59.65, 2.5)
  line L206 (-59.65, 2.5) -> (-59.65, 16.5)
  line L207 (-59.65, 16.5) -> (-63.65, 16.5)
  line L208 (-63.65, 16.5) -> (-63.65, 18)
  line L209 (-63.65, 18) -> (-69.65, 18)
  line L210 (-69.65, 18) -> (-69.65, 16.5)
  line L211 (-69.65, 16.5) -> (-73.65, 16.5)
  line L212 (-73.65, 16.5) -> (-73.65, 2.5)
  line L213 (-73.65, 2.5) -> (-69.65, 2.5)
  line L214 (-69.65, 2.5) -> (-69.65, 1)
  line L215 (-69.65, 1) -> (-63.65, 1)
  line L216 (-25.55, 21.21) -> (-25.55, 22.71)
  line L217 (-25.55, 22.71) -> (-31.55, 22.71)
  line L218 (-31.55, 22.71) -> (-31.55, 21.21)
  line L219 (-31.55, 21.21) -> (-35.55, 21.21)
  line L220 (-35.55, 21.21) -> (-35.55, 7.21)
  line L221 (-35.55, 7.21) -> (-31.55, 7.21)
  line L222 (-31.55, 7.21) -> (-31.55, 5.71)
  line L223 (-31.55, 5.71) -> (-25.55, 5.71)
  line L224 (-25.55, 5.71) -> (-25.55, 7.21)
  line L225 (-25.55, 7.21) -> (-21.55, 7.21)
  line L226 (-21.55, 7.21) -> (-21.55, 21.21)
  line L227 (-21.55, 21.21) -> (-25.55, 21.21)
  line L228 (-44.6, 55.69) -> (-44.6, 57.19)
  line L229 (-44.6, 57.19) -> (-50.6, 57.19)
  line L230 (-50.6, 57.19) -> (-50.6, 55.69)
  line L231 (-50.6, 55.69) -> (-54.6, 55.69)
  line L232 (-54.6, 55.69) -> (-54.6, 41.69)
  line L233 (-54.6, 41.69) -> (-50.6, 41.69)
  line L234 (-50.6, 41.69) -> (-50.6, 40.19)
  line L235 (-50.6, 40.19) -> (-44.6, 40.19)
  line L236 (-44.6, 40.19) -> (-44.6, 41.69)
  line L237 (-44.6, 41.69) -> (-40.6, 41.69)
  line L238 (-40.6, 41.69) -> (-40.6, 55.69)
  line L239 (-40.6, 55.69) -> (-44.6, 55.69)
  line L240 (-6.5, 79.5) -> (-6.5, 81)
  line L241 (-6.5, 81) -> (-12.5, 81)
  line L242 (-12.5, 81) -> (-12.5, 79.5)
  line L243 (-12.5, 79.5) -> (-16.5, 79.5)
  line L244 (-16.5, 79.5) -> (-16.5, 65.5)
  line L245 (-16.5, 65.5) -> (-12.5, 65.5)
  line L246 (-12.5, 65.5) -> (-12.5, 64)
  line L247 (-12.5, 64) -> (-6.5, 64)
  line L248 (-6.5, 64) -> (-6.5, 65.5)
  line L249 (-6.5, 65.5) -> (-2.5, 65.5)
  line L250 (-2.5, 65.5) -> (-2.5, 79.5)
  line L251 (-2.5, 79.5) -> (-6.5, 79.5)
  line L252 (-115.5244, 110.9346) -> (-116.1358, 109.5649)
  line L253 (-116.1358, 109.5649) -> (-119.7884, 111.1955)
  line L254 (-119.7884, 111.1955) -> (-125.4956, 98.4116)
  line L255 (-125.4956, 98.4116) -> (-121.843, 96.781)
  line L256 (-121.843, 96.781) -> (-122.4545, 95.4113)
  line L257 (-122.4545, 95.4113) -> (-116.9757, 92.9654)
  line L258 (-116.9757, 92.9654) -> (-116.3642, 94.3351)
  line L259 (-116.3642, 94.3351) -> (-112.7117, 92.7045)
  line L260 (-112.7117, 92.7045) -> (-107.0045, 105.4884)
  line L261 (-107.0045, 105.4884) -> (-110.657, 107.119)
  line L262 (-110.657, 107.119) -> (-110.0455, 108.4887)
  line L263 (-110.0455, 108.4887) -> (-115.5244, 110.9346)
  line L264 (-107.75, 78.9) -> (-107.75, 77.4)
  line L265 (-107.75, 77.4) -> (-111.75, 77.4)
  line L266 (-111.75, 77.4) -> (-111.75, 63.4)
  line L267 (-111.75, 63.4) -> (-107.75, 63.4)
  line L268 (-107.75, 63.4) -> (-107.75, 61.9)
  line L269 (-107.75, 61.9) -> (-101.75, 61.9)
  line L270 (-101.75, 61.9) -> (-101.75, 63.4)
  line L271 (-101.75, 63.4) -> (-97.75, 63.4)
  line L272 (-97.75, 63.4) -> (-97.75, 77.4)
  line L273 (-97.75, 77.4) -> (-101.75, 77.4)
  line L274 (-101.75, 77.4) -> (-101.75, 78.9)
  line L275 (-101.75, 78.9) -> (-107.75, 78.9)
  line L276 (-31.55, 79.86) -> (-31.55, 78.36)
  line L277 (-31.55, 78.36) -> (-35.55, 78.36)
  line L278 (-35.55, 78.36) -> (-35.55, 64.36)
  line L279 (-35.55, 64.36) -> (-31.55, 64.36)
  line L280 (-31.55, 64.36) -> (-31.55, 62.86)
  line L281 (-31.55, 62.86) -> (-25.55, 62.86)
  line L282 (-25.55, 62.86) -> (-25.55, 64.36)
  line L283 (-25.55, 64.36) -> (-21.55, 64.36)
  line L284 (-21.55, 64.36) -> (-21.55, 78.36)
  line L285 (-21.55, 78.36) -> (-25.55, 78.36)
  line L286 (-25.55, 78.36) -> (-25.55, 79.86)
  line L287 (-25.55, 79.86) -> (-31.55, 79.86)
  line L288 (-6.5, 83.05) -> (-6.5, 84.55)
  line L289 (-6.5, 84.55) -> (-2.5, 84.55)
  line L290 (-2.5, 84.55) -> (-2.5, 98.55)
  line L291 (-2.5, 98.55) -> (-6.5, 98.55)
  line L292 (-6.5, 98.55) -> (-6.5, 100.05)
  line L293 (-6.5, 100.05) -> (-12.5, 100.05)
  line L294 (-12.5, 100.05) -> (-12.5, 98.55)
  line L295 (-12.5, 98.55) -> (-16.5, 98.55)
  line L296 (-16.5, 98.55) -> (-16.5, 84.55)
  line L297 (-16.5, 84.55) -> (-12.5, 84.55)
  line L298 (-12.5, 84.55) -> (-12.5, 83.05)
  line L299 (-12.5, 83.05) -> (-6.5, 83.05)
  line L300 (-31.55, 60.81) -> (-31.55, 59.31)
  line L301 (-31.55, 59.31) -> (-35.55, 59.31)
  line L302 (-35.55, 59.31) -> (-35.55, 45.31)
  line L303 (-35.55, 45.31) -> (-31.55, 45.31)
  line L304 (-31.55, 45.31) -> (-31.55, 43.81)
  line L305 (-31.55, 43.81) -> (-25.55, 43.81)
  line L306 (-25.55, 43.81) -> (-25.55, 45.31)
  line L307 (-25.55, 45.31) -> (-21.55, 45.31)
  line L308 (-21.55, 45.31) -> (-21.55, 59.31)
  line L309 (-21.55, 59.31) -> (-25.55, 59.31)
  line L310 (-25.55, 59.31) -> (-25.55, 60.81)
  line L311 (-25.55, 60.81) -> (-31.55, 60.81)
  line L312 (-63.65, 20.05) -> (-63.65, 21.55)
  line L313 (-63.65, 21.55) -> (-59.65, 21.55)
  line L314 (-59.65, 21.55) -> (-59.65, 35.55)
  line L315 (-59.65, 35.55) -> (-63.65, 35.55)
  line L316 (-63.65, 35.55) -> (-63.65, 37.05)
  line L317 (-63.65, 37.05) -> (-69.65, 37.05)
  line L318 (-69.65, 37.05) -> (-69.65, 35.55)
  line L319 (-69.65, 35.55) -> (-73.65, 35.55)
  line L320 (-73.65, 35.55) -> (-73.65, 21.55)
  line L321 (-73.65, 21.55) -> (-69.65, 21.55)
  line L322 (-69.65, 21.55) -> (-69.65, 20.05)
  line L323 (-69.65, 20.05) -> (-63.65, 20.05)
  line L324 (-44.6, 21.14) -> (-44.6, 22.64)
  line L325 (-44.6, 22.64) -> (-40.6, 22.64)
  line L326 (-40.6, 22.64) -> (-40.6, 36.64)
  line L327 (-40.6, 36.64) -> (-44.6, 36.64)
  line L328 (-44.6, 36.64) -> (-44.6, 38.14)
  line L329 (-44.6, 38.14) -> (-50.6, 38.14)
  line L330 (-50.6, 38.14) -> (-50.6, 36.64)
  line L331 (-50.6, 36.64) -> (-54.6, 36.64)
  line L332 (-54.6, 36.64) -> (-54.6, 22.64)
  line L333 (-54.6, 22.64) -> (-50.6, 22.64)
  line L334 (-50.6, 22.64) -> (-50.6, 21.14)
  line L335 (-50.6, 21.14) -> (-44.6, 21.14)
  line L336 (-12.5, 23.85) -> (-12.5, 22.35)
  line L337 (-12.5, 22.35) -> (-16.5, 22.35)
  line L338 (-16.5, 22.35) -> (-16.5, 8.35)
  line L339 (-16.5, 8.35) -> (-12.5, 8.35)
  line L340 (-12.5, 8.35) -> (-12.5, 6.85)
  line L341 (-12.5, 6.85) -> (-6.5, 6.85)
  line L342 (-6.5, 6.85) -> (-6.5, 8.35)
  line L343 (-6.5, 8.35) -> (-2.5, 8.35)
  line L344 (-2.5, 8.35) -> (-2.5, 22.35)
  line L345 (-2.5, 22.35) -> (-6.5, 22.35)
  line L346 (-6.5, 22.35) -> (-6.5, 23.85)
  line L347 (-6.5, 23.85) -> (-12.5, 23.85)
  line L348 (-88.7, 19.09) -> (-88.7, 17.59)
  line L349 (-88.7, 17.59) -> (-92.7, 17.59)
  line L350 (-92.7, 17.59) -> (-92.7, 3.59)
  line L351 (-92.7, 3.59) -> (-88.7, 3.59)
  line L352 (-88.7, 3.59) -> (-88.7, 2.09)
  line L353 (-88.7, 2.09) -> (-82.7, 2.09)
  line L354 (-82.7, 2.09) -> (-82.7, 3.59)
  line L355 (-82.7, 3.59) -> (-78.7, 3.59)
  line L356 (-78.7, 3.59) -> (-78.7, 17.59)
  line L357 (-78.7, 17.59) -> (-82.7, 17.59)
  line L358 (-82.7, 17.59) -> (-82.7, 19.09)
  line L359 (-82.7, 19.09) -> (-88.7, 19.09)
  line L360 (-88.7, 57.19) -> (-88.7, 55.69)
  line L361 (-88.7, 55.69) -> (-92.7, 55.69)
  line L362 (-92.7, 55.69) -> (-92.7, 41.69)
  line L363 (-92.7, 41.69) -> (-88.7, 41.69)
  line L364 (-88.7, 41.69) -> (-88.7, 40.19)
  line L365 (-88.7, 40.19) -> (-82.7, 40.19)
  line L366 (-82.7, 40.19) -> (-82.7, 41.69)
  line L367 (-82.7, 41.69) -> (-78.7, 41.69)
  line L368 (-78.7, 41.69) -> (-78.7, 55.69)
  line L369 (-78.7, 55.69) -> (-82.7, 55.69)
  line L370 (-82.7, 55.69) -> (-82.7, 57.19)
  line L371 (-82.7, 57.19) -> (-88.7, 57.19)
  line L372 (-101.75, 23.8) -> (-101.75, 25.3)
  line L373 (-101.75, 25.3) -> (-97.75, 25.3)
  line L374 (-97.75, 25.3) -> (-97.75, 39.3)
  line L375 (-97.75, 39.3) -> (-101.75, 39.3)
  line L376 (-101.75, 39.3) -> (-101.75, 40.8)
  line L377 (-101.75, 40.8) -> (-107.75, 40.8)
  line L378 (-107.75, 40.8) -> (-107.75, 39.3)
  line L379 (-107.75, 39.3) -> (-111.75, 39.3)
  line L380 (-111.75, 39.3) -> (-111.75, 25.3)
  line L381 (-111.75, 25.3) -> (-107.75, 25.3)
  line L382 (-107.75, 25.3) -> (-107.75, 23.8)
  line L383 (-107.75, 23.8) -> (-101.75, 23.8)
  line L384 (-107.75, 21.75) -> (-107.75, 20.25)
  line L385 (-107.75, 20.25) -> (-111.75, 20.25)
  line L386 (-111.75, 20.25) -> (-111.75, 6.25)
  line L387 (-111.75, 6.25) -> (-107.75, 6.25)
  line L388 (-107.75, 6.25) -> (-107.75, 4.75)
  line L389 (-107.75, 4.75) -> (-101.75, 4.75)
  line L390 (-101.75, 4.75) -> (-101.75, 6.25)
  line L391 (-101.75, 6.25) -> (-97.75, 6.25)
  line L392 (-97.75, 6.25) -> (-97.75, 20.25)
  line L393 (-97.75, 20.25) -> (-101.75, 20.25)
  line L394 (-101.75, 20.25) -> (-101.75, 21.75)
  line L395 (-101.75, 21.75) -> (-107.75, 21.75)
  line L396 (-82.7, 21.14) -> (-82.7, 22.64)
  line L397 (-82.7, 22.64) -> (-78.7, 22.64)
  line L398 (-78.7, 22.64) -> (-78.7, 36.64)
  line L399 (-78.7, 36.64) -> (-82.7, 36.64)
  line L400 (-82.7, 36.64) -> (-82.7, 38.14)
  line L401 (-82.7, 38.14) -> (-88.7, 38.14)
  line L402 (-88.7, 38.14) -> (-88.7, 36.64)
  line L403 (-88.7, 36.64) -> (-92.7, 36.64)
  line L404 (-92.7, 36.64) -> (-92.7, 22.64)
  line L405 (-92.7, 22.64) -> (-88.7, 22.64)
  line L406 (-88.7, 22.64) -> (-88.7, 21.14)
  line L407 (-88.7, 21.14) -> (-82.7, 21.14)
  line L408 (-12.5, 42.9) -> (-12.5, 41.4)
  line L409 (-12.5, 41.4) -> (-16.5, 41.4)
  line L410 (-16.5, 41.4) -> (-16.5, 27.4)
  line L411 (-16.5, 27.4) -> (-12.5, 27.4)
  line L412 (-12.5, 27.4) -> (-12.5, 25.9)
  line L413 (-12.5, 25.9) -> (-6.5, 25.9)
  line L414 (-6.5, 25.9) -> (-6.5, 27.4)
  line L415 (-6.5, 27.4) -> (-2.5, 27.4)
  line L416 (-2.5, 27.4) -> (-2.5, 41.4)
  line L417 (-2.5, 41.4) -> (-6.5, 41.4)
  line L418 (-6.5, 41.4) -> (-6.5, 42.9)
  line L419 (-6.5, 42.9) -> (-12.5, 42.9)
  line L420 (-25.55, 24.76) -> (-25.55, 26.26)
  line L421 (-25.55, 26.26) -> (-21.55, 26.26)
  line L422 (-21.55, 26.26) -> (-21.55, 40.26)
  line L423 (-21.55, 40.26) -> (-25.55, 40.26)
  line L424 (-25.55, 40.26) -> (-25.55, 41.76)
  line L425 (-25.55, 41.76) -> (-31.55, 41.76)
  line L426 (-31.55, 41.76) -> (-31.55, 40.26)
  line L427 (-31.55, 40.26) -> (-35.55, 40.26)
  line L428 (-35.55, 40.26) -> (-35.55, 26.26)
  line L429 (-35.55, 26.26) -> (-31.55, 26.26)
  line L430 (-31.55, 26.26) -> (-31.55, 24.76)
  line L431 (-31.55, 24.76) -> (-25.55, 24.76)
  line L432 (-63.65, 39.1) -> (-63.65, 40.6)
  line L433 (-63.65, 40.6) -> (-59.65, 40.6)
  line L434 (-59.65, 40.6) -> (-59.65, 54.6)
  line L435 (-59.65, 54.6) -> (-63.65, 54.6)
  line L436 (-63.65, 54.6) -> (-63.65, 56.1)
  line L437 (-63.65, 56.1) -> (-69.65, 56.1)
  line L438 (-69.65, 56.1) -> (-69.65, 54.6)
  line L439 (-69.65, 54.6) -> (-73.65, 54.6)
  line L440 (-73.65, 54.6) -> (-73.65, 40.6)
  line L441 (-73.65, 40.6) -> (-69.65, 40.6)
  line L442 (-69.65, 40.6) -> (-69.65, 39.1)
  line L443 (-69.65, 39.1) -> (-63.65, 39.1)
  line L444 (-25.55, 81.91) -> (-25.55, 83.41)
  line L445 (-25.55, 83.41) -> (-21.55, 83.41)
  line L446 (-21.55, 83.41) -> (-21.55, 97.41)
  line L447 (-21.55, 97.41) -> (-25.55, 97.41)
  line L448 (-25.55, 97.41) -> (-25.55, 98.91)
  line L449 (-25.55, 98.91) -> (-31.55, 98.91)
  line L450 (-31.55, 98.91) -> (-31.55, 97.41)
  line L451 (-31.55, 97.41) -> (-35.55, 97.41)
  line L452 (-35.55, 97.41) -> (-35.55, 83.41)
  line L453 (-35.55, 83.41) -> (-31.55, 83.41)
  line L454 (-31.55, 83.41) -> (-31.55, 81.91)
  line L455 (-31.55, 81.91) -> (-25.55, 81.91)
  line L456 (-50.6, 76.24) -> (-50.6, 74.74)
  line L457 (-50.6, 74.74) -> (-54.6, 74.74)
  line L458 (-54.6, 74.74) -> (-54.6, 60.74)
  line L459 (-54.6, 60.74) -> (-50.6, 60.74)
  line L460 (-50.6, 60.74) -> (-50.6, 59.24)
  line L461 (-50.6, 59.24) -> (-44.6, 59.24)
  line L462 (-44.6, 59.24) -> (-44.6, 60.74)
  line L463 (-44.6, 60.74) -> (-40.6, 60.74)
  line L464 (-40.6, 60.74) -> (-40.6, 74.74)
  line L465 (-40.6, 74.74) -> (-44.6, 74.74)
  line L466 (-44.6, 74.74) -> (-44.6, 76.24)
  line L467 (-44.6, 76.24) -> (-50.6, 76.24)
  line L468 (-63.65, 77.2) -> (-63.65, 78.7)
  line L469 (-63.65, 78.7) -> (-59.65, 78.7)
  line L470 (-59.65, 78.7) -> (-59.65, 92.7)
  line L471 (-59.65, 92.7) -> (-63.65, 92.7)
  line L472 (-63.65, 92.7) -> (-63.65, 94.2)
  line L473 (-63.65, 94.2) -> (-69.65, 94.2)
  line L474 (-69.65, 94.2) -> (-69.65, 92.7)
  line L475 (-69.65, 92.7) -> (-73.65, 92.7)
  line L476 (-73.65, 92.7) -> (-73.65, 78.7)
  line L477 (-73.65, 78.7) -> (-69.65, 78.7)
  line L478 (-69.65, 78.7) -> (-69.65, 77.2)
  line L479 (-69.65, 77.2) -> (-63.65, 77.2)
  line L480 (-88.7, 76.24) -> (-88.7, 74.74)
  line L481 (-88.7, 74.74) -> (-92.7, 74.74)
  line L482 (-92.7, 74.74) -> (-92.7, 60.74)
  line L483 (-92.7, 60.74) -> (-88.7, 60.74)
  line L484 (-88.7, 60.74) -> (-88.7, 59.24)
  line L485 (-88.7, 59.24) -> (-82.7, 59.24)
  line L486 (-82.7, 59.24) -> (-82.7, 60.74)
  line L487 (-82.7, 60.74) -> (-78.7, 60.74)
  line L488 (-78.7, 60.74) -> (-78.7, 74.74)
  line L489 (-78.7, 74.74) -> (-82.7, 74.74)
  line L490 (-82.7, 74.74) -> (-82.7, 76.24)
  line L491 (-82.7, 76.24) -> (-88.7, 76.24)
  line L492 (-92.9744, 101.2746) -> (-93.5858, 99.9049)
  line L493 (-93.5858, 99.9049) -> (-97.2384, 101.5355)
  line L494 (-97.2384, 101.5355) -> (-102.9456, 88.7516)
  line L495 (-102.9456, 88.7516) -> (-99.293, 87.121)
  line L496 (-99.293, 87.121) -> (-99.9045, 85.7513)
  line L497 (-99.9045, 85.7513) -> (-94.4257, 83.3054)
  line L498 (-94.4257, 83.3054) -> (-93.8142, 84.6751)
  line L499 (-93.8142, 84.6751) -> (-90.1617, 83.0445)
  line L500 (-90.1617, 83.0445) -> (-84.4545, 95.8284)
  line L501 (-84.4545, 95.8284) -> (-88.107, 97.459)
  line L502 (-88.107, 97.459) -> (-87.4955, 98.8287)
  line L503 (-87.4955, 98.8287) -> (-92.9744, 101.2746)
  circle A12 centre (-135.75, 5.5028) radius 2.8
  circle A13 centre (-135.75, 5.5028) radius 1.65
  line L504 (-133.0743, 4.6778) -> (-138.4257, 4.6778)
  line L505 (-133.0743, 6.3278) -> (-138.4257, 6.3278)
  line L506 (-134.925, 2.8271) -> (-134.925, 8.1785)
  line L507 (-136.575, 2.8271) -> (-136.575, 8.1785)
  line L508 (-67.625, 0.0028) -> (-67.625, 103)
  line L509 (6, 51.5014) -> (-141.25, 51.5014)
  line L510 (1.325, 2.8271) -> (1.325, 8.1785)
  line L511 (-0.325, 2.8271) -> (-0.325, 8.1785)
  line L512 (-2.1757, 6.3278) -> (3.1757, 6.3278)
  line L513 (-2.1757, 4.6778) -> (3.1757, 4.6778)
  circle A14 centre (0.5, 5.5028) radius 2.8
  circle A15 centre (0.5, 5.5028) radius 1.65
  circle A16 centre (0.5, 97.5) radius 1.65
  line L514 (1.325, 100.1757) -> (1.325, 94.8243)
  line L515 (-2.1757, 98.325) -> (3.1757, 98.325)
  circle A17 centre (0.5, 97.5) radius 2.8